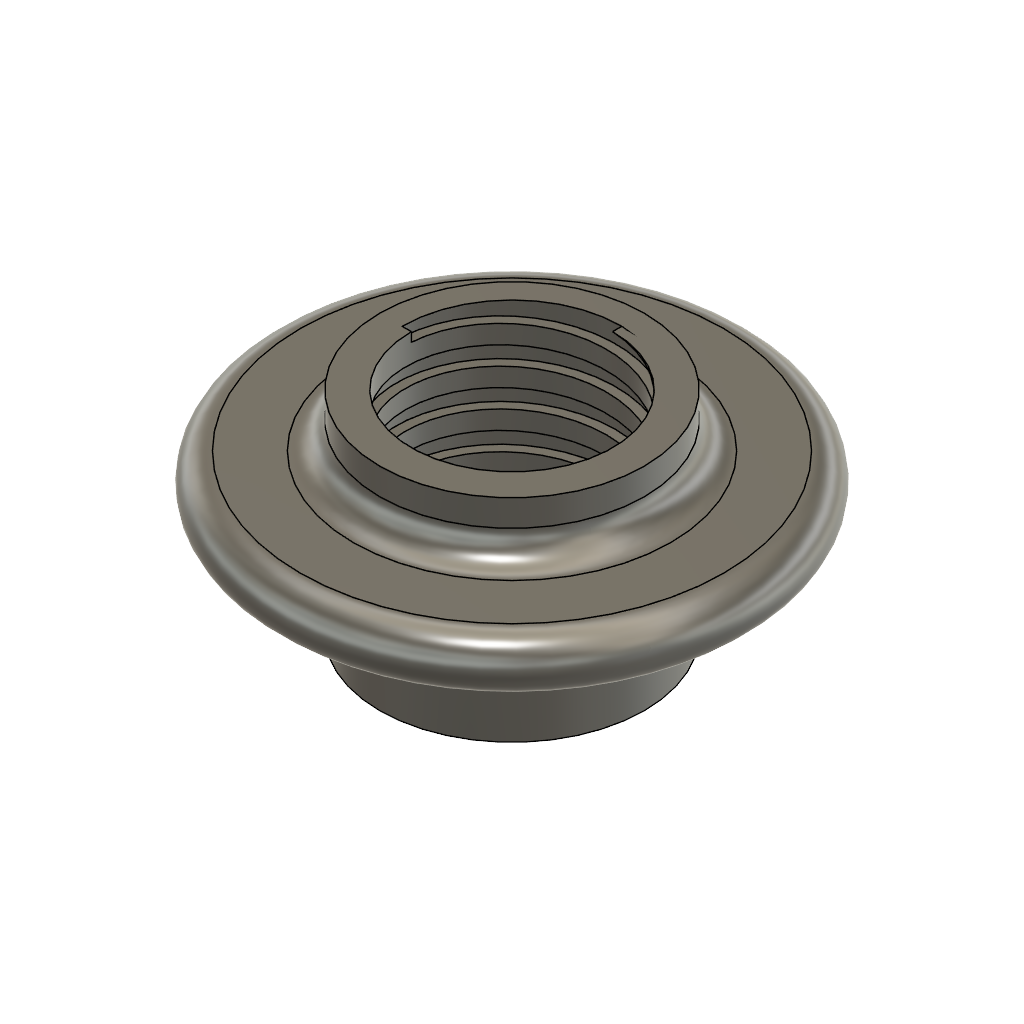
nut (Autodesk Fusion 360 design; units mm, degrees)
part number: 2026-11-04-17-30-57-676
Autodesk Fusion 360 part; units mm, degrees
sketch "Sketch1" plane through (0, 0, 0) normal (0, 1, 0) x (1, 0, 0)
  circle A0 centre (0, 0) radius 25
  dimension "d1" = 50
  constraint coincident A0.centre origin
  measures "d1" diameter of A0
extrude "Extrude1" add sketch "Sketch1" along normal blind 20
sketch "Sketch2" plane through (0, 20, 0) normal (0, 1, 0) x (-1, 0, 0)
  circle A0 centre (0, 0) radius 25
  circle A1 centre (0, 0) radius 45
  dimension "d4" = 90
  constraint coincident A0.centre A1.centre
  measures "d4" diameter of A1
extrude "Extrude2" add sketch "Sketch2" along normal blind 10 contours A0 | A1
sketch "Sketch3" plane through (0, 30, 0) normal (0, 1, 0) x (-1, 0, 0)
  circle A0 centre (0, 0) radius 45
  circle A1 centre (0, 0) radius 25
  dimension "d7" = 50
  constraint coincident A0.centre A1.centre
  measures "d7" diameter of A1
extrude "Extrude3" add sketch "Sketch3" along normal blind 10 contours A1
fillet "Fillet1" radius 5 1 edges at (23.3082, 30, 9.0404)
fillet "Fillet2" radius 5 1 edges at (-23.3082, 20, 9.0404)
fillet "Fillet3" radius 5 1 edges at (41.9547, 30, -16.2727)
fillet "Fillet4" radius 5 1 edges at (41.9547, 20, -16.2727)
sketch "Sketch4" plane through (0, 40, 0) normal (0, 1, 0) x (-1, 0, 0)
  circle A0 centre (0, 0) radius 25
  circle A1 centre (0, 0) radius 19
  dimension "d18" = 38
  constraint coincident A0.centre A1.centre
  measures "d18" diameter of A1
extrude "Extrude4" cut sketch "Sketch4" against normal blind 45 contours A1
coil "CoilPrimitive1" cut diameter 38 section square size 3.5 on centre turns 6.42857 pitch 7 right hand placed x (-1, 0, 0) y (0, 0, -1) z (0, -1, 0) at (0, 40, 0)
